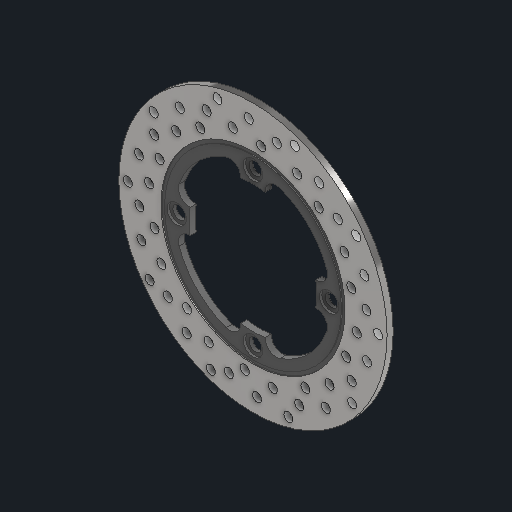
# Autodesk Inventor part: F3_Brake_Rotor_V2
Saved by Autodesk Inventor 2027.1 (Build 311270010, 270A)
## iProperties
Created: 2026-10-10
Part Number: F3_Brake_Rotor_V2
Material: Generic
Document SubType Name: Modeling
Designer: share
Density: 1 g/cm^3
Appearance: Default
Author: share
Autodesk Inventor part; units mm, degrees
ref_plane "YZ Plane" through (0, 0, 0) normal (1, 0, 0) x (0, 1, 0)
ref_plane "XZ Plane" through (0, 0, 0) normal (0, 1, 0) x (-1, 0, 0)
ref_plane "XY Plane" through (0, 0, 0) normal (0, 0, 1) x (1, 0, 0)
sketch "Sketch1" plane through (0, 0, 0) normal (0, 0, 1) x (1, 0, 0)
  circle A0 centre (0, 0) radius 110
  circle A1 centre (0, 0) radius 75.5
  dimension "d0" = 220
  dimension "d1" = 34.5
  constraints: 2 centre point, 2 coincident
  measures "d0" diameter of A0
  measures "d1" radial gap between concentric circles of A1 A0
extrude "Extrusion1" add sketch "Sketch1" along normal mid plane 5
sketch "Sketch2" plane through (0, 0, 0) normal (0, 0, 1) x (1, 0, 0)
  circle A0 centre (0, 0) radius 75.5 projected
  circle A1 centre (0, 0) radius 72.5
  dimension "d4" = 3
  constraints: 1 centre point, 1 coincident
  measures "d4" radial gap between concentric circles of A1 A0
extrude "Extrusion2" add sketch "Sketch2" along normal mid plane 3
sketch "Sketch3" plane through (0, 0, 0) normal (0, 0, 1) x (1, 0, 0)
  circle A0 centre (0, 0) radius 72.5 projected
  line L0 (0, 154) -> (0, -154) construction
  line L1 (-154, 0) -> (154, 0) construction
  arc A1 (-60.6115, 22.0566) -> (-51.5388, 10) centre (-52.1541, 18.9789) ccw
  arc A2 (-51.5388, -10) -> (-60.6115, -22.0566) centre (-52.1541, -18.9789) ccw
  arc A3 (-22.0566, -60.6115) -> (-10, -51.5388) centre (-18.9789, -52.1541) ccw
  arc A4 (10, -51.5388) -> (22.0566, -60.6115) centre (18.9789, -52.1541) ccw
  arc A5 (60.6115, -22.0566) -> (51.5388, -10) centre (52.1541, -18.9789) ccw
  arc A6 (51.5388, 10) -> (60.6115, 22.0566) centre (52.1541, 18.9789) ccw
  arc A7 (22.0566, 60.6115) -> (10, 51.5388) centre (18.9789, 52.1541) ccw
  arc A8 (-10, 51.5388) -> (-22.0566, 60.6115) centre (-18.9789, 52.1541) ccw
  arc A9 (10, 51.5388) -> (-10, 51.5388) centre (0, 0) ccw
  arc A10 (51.5388, -10) -> (51.5388, 10) centre (0, 0) ccw
  arc A11 (-51.5388, 10) -> (-51.5388, -10) centre (0, 0) ccw
  arc A12 (-10, -51.5388) -> (10, -51.5388) centre (0, 0) ccw
  arc A13 (60.6115, 22.0566) -> (22.0566, 60.6115) centre (0, 0) ccw
  arc A14 (22.0566, -60.6115) -> (60.6115, -22.0566) centre (0, 0) ccw
  arc A15 (-22.0566, 60.6115) -> (-60.6115, 22.0566) centre (0, 0) ccw
  arc A16 (-60.6115, -22.0566) -> (-22.0566, -60.6115) centre (0, 0) ccw
  dimension "d9" = 9
  dimension "d10" = 10
  dimension "d14" = 360
  dimension "d16" = 52.5
  dimension "d18" = 8
  constraints: 32 point on circle, 16 centre point, 3 symmetric about line, 2 coincident, 1 tangent, 34 other
  measures "d9" radius of A1
  measures "d10" distance from line of L1 A1.end
  measures "d16" radius of A11
  measures "d18" radial gap between concentric circles of A0 A16
extrude "Extrusion3" add sketch "Sketch3" along normal mid plane 5
sketch "Sketch4" plane through (0, 0, 2.5) normal (0, 0, 1) x (1, 0, 0)
  circle A0 centre (0, 0) radius 62.5
  line L0 (0, 154) -> (0, -154) construction
  line L1 (-154, 0) -> (154, 0) construction
  point P0 (0, 62.5)
  point P1 (62.5, 0)
  point P2 (-62.5, 0)
  point P3 (0, -62.5)
  dimension "d21" = 125
  constraints: 4 point on circle, 4 point on line, 1 centre point, 1 coincident
  measures "d21" diameter of A0
hole "Hole1" at (0, 62.5, 2.5) at (62.5, 0, 2.5) at (-62.5, 0, 2.5) at (0, -62.5, 2.5) direction (0, 0, -1) diameter 10.5 end through all counterbore diameter 16 counterbore depth 2
sketch "Sketch5" plane through (0, 0, 2.5) normal (0, 0, 1) x (1, 0, 0)
  circle A0 centre (0, 0) radius 75.5 construction
  circle A1 centre (0, 0) radius 110 construction
  line L0 (0, 154) -> (0, -154) construction
  line L1 (-154, 0) -> (154, 0) construction
  arc A2 (50, 97.9796) -> (0, 75.5) centre (46.8858, 38.0605) ccw construction
  circle A3 centre (6.738, 82.6492) radius 3.75
  circle A4 centre (19.6464, 91.5209) radius 3.75
  circle A5 centre (34.4111, 96.7493) radius 3.75
  line L2 (46.8858, 38.0605) -> (6.738, 82.6492) construction
  line L3 (46.8858, 38.0605) -> (19.6464, 91.5209) construction
  line L4 (46.8858, 38.0605) -> (34.4111, 96.7493) construction
  arc A6 (75, 80.4674) -> (20, 72.8028) centre (63.6132, -38.9911) ccw construction
  circle A7 centre (36.2264, 77.8419) radius 3.75
  circle A8 centre (54.3963, 80.6544) radius 3.75
  line L5 (36.2264, 77.8419) -> (46.8858, 38.0605)
  line L6 (54.3963, 80.6544) -> (46.8858, 38.0605)
  dimension "d29" = 60
  dimension "d30" = 50
  dimension "d31" = 48
  dimension "d32" = 63
  dimension "d33" = 78
  dimension "d34" = 7.5
  dimension "d40" = 120
  dimension "d41" = 75
  dimension "d42" = 20
  dimension "d43" = 75
  dimension "d44" = 100
  constraints: 13 point on circle, 10 end point, 7 centre point, 4 equal radius, 1 point on line
  measures "d29" radius of A2
  measures "d30" distance from line of A1.start L0
  measures "d31" angle of L1 L2
  measures "d32" angle of L1 L3
  measures "d33" angle of L1 L4
  measures "d34" diameter of A5
  measures "d40" radius of A6
  measures "d41" distance from line of L0 A1.end
  measures "d42" distance from line of L0 A0.end
  measures "d43" angle of L1 L5
  measures "d44" angle of L1 L6
extrude "Extrusion4" cut sketch "Sketch5" against normal through all
pattern_circular "Circular Pattern1" count 10 over 360 about axis through (0, 0, -10) along (0, 0, 1) of "Extrusion4"
body "Solid1"
